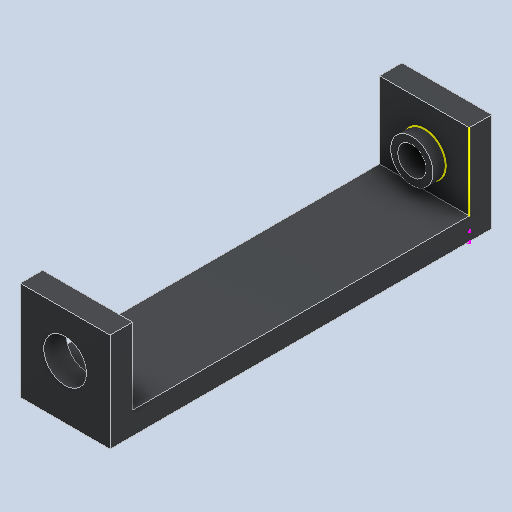
# Autodesk Inventor part: Pieza8
Saved by Autodesk Inventor 2025.3 (Build 293356000, 356)
## iProperties
Created: 2026-09-21
Part Number: Pieza8
Material: PLA (ácido poliláctico) - FDM nominal
Document SubType Name: Modeling
Designer: STEVEN LONDOÑO
Density: 1.24 g/cm^3
Appearance: PLA negro mate - capas FDM
Author: STEVEN LONDOÑO
Autodesk Inventor part; units mm, degrees
ref_plane "YZ Plane" through (0, 0, 0) normal (1, 0, 0) x (0, 1, 0)
ref_plane "XZ Plane" through (0, 0, 0) normal (0, 1, 0) x (-1, 0, 0)
ref_plane "XY Plane" through (0, 0, 0) normal (0, 0, 1) x (1, 0, 0)
sketch "Boceto1" plane through (0, 0, 0) normal (0, 0, 1) x (1, 0, 0)
  line L0 (-10, 10) -> (-10, -10)
  line L1 (10, -10) -> (10, 10)
  line L2 (10, 10) -> (-10, 10)
  circle A0 centre (0, 0) radius 3.155
  circle A1 centre (0, 0) radius 4.75
  line L3 (-10, -10) -> (-10, -12)
  line L4 (-10, -12) -> (10, -12)
  line L5 (10, -12) -> (10, -10)
  line L6 (0, -7) -> (10, -7)
  line L7 (0, -7) -> (-10, -7)
  point P0 (-10, 0)
  point P1 (0, -10)
  dimension "d0" = 20
  dimension "d1" = 20
  dimension "d2" = 6.31
  dimension "d3" = 9.5
  dimension "d9" = 2
  constraints: 16 end point, 4 perpendicular, 3 point on line, 2 centre point, 2 coincident, 2 vertical, 1 horizontal alignment, 1 midpoint, 1 vertical alignment
  measures "d0" distance of L0.start L0.end
  measures "d1" distance of L0.end L1.start
  measures "d2" diameter of A0
  measures "d3" diameter of A1
  measures "d9" distance of L0.end L3.end
extrude "Extrusión1" add sketch "Boceto1" along normal blind 5 contours L2 L1 L6 L7 L0
sketch "Boceto2" plane through (0, 0, 0) normal (0, 0, -1) x (-1, 0, 0)
  circle A0 centre (0, 0) radius 3.155
  circle A1 centre (0, 0) radius 4.75
  dimension "d6" = 6.31
  constraints: 2 centre point, 2 coincident
  measures "d6" diameter of A0
extrude "Extrusión2" add sketch "Boceto2" against normal blind 7.8
sketch "Boceto3" plane through (0, 0, 5) normal (0, 0, 1) x (1, 0, 0)
  circle A0 centre (0, 0) radius 4.75 projected
  line L0 (10, -7) -> (10, 10) projected
  point P0 (10, -10)
  point P1 (10, -12)
extrude "Extrusión3" add sketch "Boceto1" along normal blind 85 contours L7 L6 L1 L5 L4 L3 L0
sketch "Boceto4" plane through (0, 0, 85) normal (0, 0, 1) x (1, 0, 0)
  line L0 (10, 10) -> (-10, 10) projected
  line L1 (10, -12) -> (10, 10)
  line L2 (10, 10) -> (-10, 10)
  line L3 (-10, 10) -> (-10, -12)
  line L4 (-10, -12) -> (10, -12)
  circle A0 centre (0, 0) radius 3.155 projected
  circle A1 centre (0, 0) radius 3.155
  circle A2 centre (0, 0) radius 4.75
  dimension "d13" = 9.5
  constraints: 8 end point, 2 centre point, 2 coincident, 2 perpendicular, 1 collinear, 1 vertical
  measures "d13" diameter of A2
extrude "Extrusión4" add sketch "Boceto4" against normal blind 5 contours L1 L4 L3 L0
